Autodesk Fusion 360 part; units mm, degrees
(part 7 of 8)
equation "d1141 = ( ( ( keyRowOne ) + holderSpringY ) - holderSpringWidth / 2 ) + faceOriginV"
equation "d1142 = ( ( ( layoutGap + keycapSize / 2 + 2 * keyPitch ) - holderFrameX / 2 ) + ( holderFrameX / 2 - holderWidth / 2 + holderHookOverlap ) ) - ( ( layoutGap + keycapSize / 2 + 2 * keyPitch ) - holderFrameX / 2 )"
equation "d1143 = ( ( ( ( ( keyRowOne ) + holderSpringY ) - holderSpringWidth / 2 ) + faceOriginV ) + ( holderSpringWidth ) ) - ( ( ( ( keyRowOne ) + holderSpringY ) - holderSpringWidth / 2 ) + faceOriginV )"
equation "d1144 = -( holderHookThickness )"
equation "d1147 = ( layoutGap + keycapSize / 2 + 2 * keyPitch ) + holderWidth / 2 + holderFit"
equation "d1148 = ( ( ( keyRowOne ) + holderSpringY ) - holderSpringWidth / 2 - 0.6 mm ) + faceOriginV"
equation "d1149 = ( ( ( layoutGap + keycapSize / 2 + 2 * keyPitch ) + holderWidth / 2 + holderFit ) + ( holderFrameX / 2 - holderWidth / 2 - holderFit + 0.1 mm ) ) - ( ( layoutGap + keycapSize / 2 + 2 * keyPitch ) + holderWidth / 2 + holderFit )"
equation "d1150 = ( ( ( ( ( keyRowOne ) + holderSpringY ) - holderSpringWidth / 2 - 0.6 mm ) + faceOriginV ) + ( 0.6 mm ) ) - ( ( ( ( keyRowOne ) + holderSpringY ) - holderSpringWidth / 2 - 0.6 mm ) + faceOriginV )"
equation "d1151 = -( holderBottomDepth + holderHookThickness - shellWall - carrierClearance - carrierThickness - 1 mm + 0.2 mm )"
equation "d1153 = ( layoutGap + keycapSize / 2 + 2 * keyPitch ) + holderWidth / 2 + holderFit"
equation "d1154 = ( ( ( keyRowOne ) + holderSpringY ) + holderSpringWidth / 2 ) + faceOriginV"
equation "d1155 = ( ( ( layoutGap + keycapSize / 2 + 2 * keyPitch ) + holderWidth / 2 + holderFit ) + ( holderFrameX / 2 - holderWidth / 2 - holderFit + 0.1 mm ) ) - ( ( layoutGap + keycapSize / 2 + 2 * keyPitch ) + holderWidth / 2 + holderFit )"
equation "d1156 = ( ( ( ( ( keyRowOne ) + holderSpringY ) + holderSpringWidth / 2 ) + faceOriginV ) + ( 0.6 mm ) ) - ( ( ( ( keyRowOne ) + holderSpringY ) + holderSpringWidth / 2 ) + faceOriginV )"
equation "d1157 = -( holderBottomDepth + holderHookThickness - shellWall - carrierClearance - carrierThickness - 1 mm + 0.2 mm )"
equation "d1159 = ( layoutGap + keycapSize / 2 + 2 * keyPitch ) + holderWidth / 2 + holderFit"
equation "d1160 = ( ( ( keyRowOne ) + holderSpringY ) - holderSpringWidth / 2 ) + faceOriginV"
equation "d1161 = ( ( ( layoutGap + keycapSize / 2 + 2 * keyPitch ) + holderWidth / 2 + holderFit ) + ( holderFrameX / 2 - 0.8 mm - holderWidth / 2 - holderFit ) ) - ( ( layoutGap + keycapSize / 2 + 2 * keyPitch ) + holderWidth / 2 + holderFit )"
equation "d1162 = ( ( ( ( ( keyRowOne ) + holderSpringY ) - holderSpringWidth / 2 ) + faceOriginV ) + ( holderSpringWidth ) ) - ( ( ( ( keyRowOne ) + holderSpringY ) - holderSpringWidth / 2 ) + faceOriginV )"
equation "d1163 = -( holderHeight + holderHookThickness + 0.2 mm )"
equation "d1165 = ( layoutGap + keycapSize / 2 + 2 * keyPitch ) + holderWidth / 2 - holderHookOverlap"
equation "d1166 = ( ( ( keyRowOne ) + holderSpringY ) - holderSpringWidth / 2 ) + faceOriginV"
equation "d1167 = ( ( ( layoutGap + keycapSize / 2 + 2 * keyPitch ) + holderWidth / 2 - holderHookOverlap ) + ( holderFrameX / 2 - holderWidth / 2 + holderHookOverlap ) ) - ( ( layoutGap + keycapSize / 2 + 2 * keyPitch ) + holderWidth / 2 - holderHookOverlap )"
equation "d1168 = ( ( ( ( ( keyRowOne ) + holderSpringY ) - holderSpringWidth / 2 ) + faceOriginV ) + ( holderSpringWidth ) ) - ( ( ( ( keyRowOne ) + holderSpringY ) - holderSpringWidth / 2 ) + faceOriginV )"
equation "d1169 = -( holderHookThickness )"
equation "d1172 = ( layoutGap + keycapSize / 2 + 2 * keyPitch ) + ( -2.5 mm ) - 1.2 mm"
equation "d1173 = ( ( ( keyRowOne ) - 1.2 mm ) * cos(caseTilt) + ( holderBottomDepth + holderLidGap ) * sin(caseTilt) ) - 2.5 mm"
equation "d1174 = ( ( ( layoutGap + keycapSize / 2 + 2 * keyPitch ) + ( -2.5 mm ) - 1.2 mm ) + ( 2.4 mm ) ) - ( ( layoutGap + keycapSize / 2 + 2 * keyPitch ) + ( -2.5 mm ) - 1.2 mm )"
equation "d1175 = ( ( ( ( ( keyRowOne ) - 1.2 mm ) * cos(caseTilt) + ( holderBottomDepth + holderLidGap ) * sin(caseTilt) ) - 2.5 mm ) + ( 5 mm ) ) - ( ( ( ( keyRowOne ) - 1.2 mm ) * cos(caseTilt) + ( holderBottomDepth + holderLidGap ) * sin(caseTilt) ) - 2.5 mm )"
equation "d1176 = ( frontHeight + ( ( keyRowOne ) - 1.2 mm ) * sin(caseTilt) - ( holderBottomDepth + holderLidGap ) * cos(caseTilt) ) - bottomThickness - 2 mm"
equation "d1178 = ( layoutGap + keycapSize / 2 + 2 * keyPitch ) + ( -2.5 mm ) - 0.5 mm"
equation "d1179 = ( ( ( keyRowOne ) - 1.2 mm ) * cos(caseTilt) + ( holderBottomDepth + holderLidGap ) * sin(caseTilt) ) - 1.5 mm"
equation "d1180 = ( ( ( layoutGap + keycapSize / 2 + 2 * keyPitch ) + ( -2.5 mm ) - 0.5 mm ) + ( 1 mm ) ) - ( ( layoutGap + keycapSize / 2 + 2 * keyPitch ) + ( -2.5 mm ) - 0.5 mm )"
equation "d1181 = ( ( ( ( ( keyRowOne ) - 1.2 mm ) * cos(caseTilt) + ( holderBottomDepth + holderLidGap ) * sin(caseTilt) ) - 1.5 mm ) + ( 3 mm ) ) - ( ( ( ( keyRowOne ) - 1.2 mm ) * cos(caseTilt) + ( holderBottomDepth + holderLidGap ) * sin(caseTilt) ) - 1.5 mm )"
equation "d1182 = ( frontHeight + ( ( keyRowOne ) - 1.2 mm ) * sin(caseTilt) - ( holderBottomDepth + holderLidGap ) * cos(caseTilt) ) - bottomThickness + 0.5 mm"
equation "d1184 = ( ( layoutGap + keycapSize / 2 + 2 * keyPitch ) + ( -2.5 mm ) - 0.5 mm ) - 0.1 mm"
equation "d1185 = ( ( ( keyRowOne ) - 1.2 mm ) - 2 mm ) + faceOriginV"
equation "d1186 = ( ( ( ( layoutGap + keycapSize / 2 + 2 * keyPitch ) + ( -2.5 mm ) - 0.5 mm ) - 0.1 mm ) + ( 1.2 mm ) ) - ( ( ( layoutGap + keycapSize / 2 + 2 * keyPitch ) + ( -2.5 mm ) - 0.5 mm ) - 0.1 mm )"
equation "d1187 = ( ( ( ( ( keyRowOne ) - 1.2 mm ) - 2 mm ) + faceOriginV ) + ( 4 mm ) ) - ( ( ( ( keyRowOne ) - 1.2 mm ) - 2 mm ) + faceOriginV )"
equation "d1188 = rearHeight"
equation "d1190 = ( layoutGap + keycapSize / 2 + 2 * keyPitch ) + ( 2.5 mm ) - 1.2 mm"
equation "d1191 = ( ( ( keyRowOne ) - 1.2 mm ) * cos(caseTilt) + ( holderBottomDepth + holderLidGap ) * sin(caseTilt) ) - 2.5 mm"
equation "d1192 = ( ( ( layoutGap + keycapSize / 2 + 2 * keyPitch ) + ( 2.5 mm ) - 1.2 mm ) + ( 2.4 mm ) ) - ( ( layoutGap + keycapSize / 2 + 2 * keyPitch ) + ( 2.5 mm ) - 1.2 mm )"
equation "d1193 = ( ( ( ( ( keyRowOne ) - 1.2 mm ) * cos(caseTilt) + ( holderBottomDepth + holderLidGap ) * sin(caseTilt) ) - 2.5 mm ) + ( 5 mm ) ) - ( ( ( ( keyRowOne ) - 1.2 mm ) * cos(caseTilt) + ( holderBottomDepth + holderLidGap ) * sin(caseTilt) ) - 2.5 mm )"
equation "d1194 = ( frontHeight + ( ( keyRowOne ) - 1.2 mm ) * sin(caseTilt) - ( holderBottomDepth + holderLidGap ) * cos(caseTilt) ) - bottomThickness - 2 mm"
equation "d1196 = ( layoutGap + keycapSize / 2 + 2 * keyPitch ) + ( 2.5 mm ) - 0.5 mm"
equation "d1197 = ( ( ( keyRowOne ) - 1.2 mm ) * cos(caseTilt) + ( holderBottomDepth + holderLidGap ) * sin(caseTilt) ) - 1.5 mm"
equation "d1198 = ( ( ( layoutGap + keycapSize / 2 + 2 * keyPitch ) + ( 2.5 mm ) - 0.5 mm ) + ( 1 mm ) ) - ( ( layoutGap + keycapSize / 2 + 2 * keyPitch ) + ( 2.5 mm ) - 0.5 mm )"
equation "d1199 = ( ( ( ( ( keyRowOne ) - 1.2 mm ) * cos(caseTilt) + ( holderBottomDepth + holderLidGap ) * sin(caseTilt) ) - 1.5 mm ) + ( 3 mm ) ) - ( ( ( ( keyRowOne ) - 1.2 mm ) * cos(caseTilt) + ( holderBottomDepth + holderLidGap ) * sin(caseTilt) ) - 1.5 mm )"
equation "d1200 = ( frontHeight + ( ( keyRowOne ) - 1.2 mm ) * sin(caseTilt) - ( holderBottomDepth + holderLidGap ) * cos(caseTilt) ) - bottomThickness + 0.5 mm"
equation "d1202 = ( ( layoutGap + keycapSize / 2 + 2 * keyPitch ) + ( 2.5 mm ) - 0.5 mm ) - 0.1 mm"
equation "d1203 = ( ( ( keyRowOne ) - 1.2 mm ) - 2 mm ) + faceOriginV"
equation "d1204 = ( ( ( ( layoutGap + keycapSize / 2 + 2 * keyPitch ) + ( 2.5 mm ) - 0.5 mm ) - 0.1 mm ) + ( 1.2 mm ) ) - ( ( ( layoutGap + keycapSize / 2 + 2 * keyPitch ) + ( 2.5 mm ) - 0.5 mm ) - 0.1 mm )"
equation "d1205 = ( ( ( ( ( keyRowOne ) - 1.2 mm ) - 2 mm ) + faceOriginV ) + ( 4 mm ) ) - ( ( ( ( keyRowOne ) - 1.2 mm ) - 2 mm ) + faceOriginV )"
equation "d1206 = rearHeight"
equation "d1208 = ( layoutGap + keycapSize / 2 + 0 * keyPitch ) - holderFrameX / 2"
equation "d1209 = ( ( keyRowTwo ) - holderFrameY / 2 ) + faceOriginV"
equation "d1210 = ( ( ( layoutGap + keycapSize / 2 + 0 * keyPitch ) - holderFrameX / 2 ) + ( holderFrameX ) ) - ( ( layoutGap + keycapSize / 2 + 0 * keyPitch ) - holderFrameX / 2 )"
equation "d1211 = ( ( ( ( keyRowTwo ) - holderFrameY / 2 ) + faceOriginV ) + ( holderFrameY ) ) - ( ( ( keyRowTwo ) - holderFrameY / 2 ) + faceOriginV )"
equation "d1212 = -( holderBottomDepth + holderHookThickness - shellWall - carrierClearance - carrierThickness )"
equation "d1214 = ( layoutGap + keycapSize / 2 + 0 * keyPitch ) - holderSwitchVoid / 2"
equation "d1215 = ( ( keyRowTwo ) - holderSwitchVoid / 2 ) + faceOriginV"
equation "d1216 = ( ( ( layoutGap + keycapSize / 2 + 0 * keyPitch ) - holderSwitchVoid / 2 ) + ( holderSwitchVoid ) ) - ( ( layoutGap + keycapSize / 2 + 0 * keyPitch ) - holderSwitchVoid / 2 )"
equation "d1217 = ( ( ( ( keyRowTwo ) - holderSwitchVoid / 2 ) + faceOriginV ) + ( holderSwitchVoid ) ) - ( ( ( keyRowTwo ) - holderSwitchVoid / 2 ) + faceOriginV )"
equation "d1218 = -( holderTopDepth - shellWall - carrierClearance - carrierThickness )"
equation "d1220 = ( layoutGap + keycapSize / 2 + 0 * keyPitch ) - holderWidth / 2 - holderFit"
equation "d1221 = ( ( keyRowTwo ) - holderLength / 2 - holderFit ) + faceOriginV"
equation "d1222 = ( ( ( layoutGap + keycapSize / 2 + 0 * keyPitch ) - holderWidth / 2 - holderFit ) + ( holderWidth + 2 * holderFit ) ) - ( ( layoutGap + keycapSize / 2 + 0 * keyPitch ) - holderWidth / 2 - holderFit )"
equation "d1223 = ( ( ( ( keyRowTwo ) - holderLength / 2 - holderFit ) + faceOriginV ) + ( holderLength + 2 * holderFit ) ) - ( ( ( keyRowTwo ) - holderLength / 2 - holderFit ) + faceOriginV )"
equation "d1224 = -( holderHeight + holderHookThickness + 0.2 mm )"
equation "d1226 = ( layoutGap + keycapSize / 2 + 0 * keyPitch ) - holderFrameX / 2 - 0.1 mm"
equation "d1227 = ( ( ( keyRowTwo ) + holderSpringY ) - holderSpringWidth / 2 - 0.6 mm ) + faceOriginV"
equation "d1228 = ( ( ( layoutGap + keycapSize / 2 + 0 * keyPitch ) - holderFrameX / 2 - 0.1 mm ) + ( holderFrameX / 2 - holderWidth / 2 - holderFit + 0.1 mm ) ) - ( ( layoutGap + keycapSize / 2 + 0 * keyPitch ) - holderFrameX / 2 - 0.1 mm )"
equation "d1229 = ( ( ( ( ( keyRowTwo ) + holderSpringY ) - holderSpringWidth / 2 - 0.6 mm ) + faceOriginV ) + ( 0.6 mm ) ) - ( ( ( ( keyRowTwo ) + holderSpringY ) - holderSpringWidth / 2 - 0.6 mm ) + faceOriginV )"
equation "d1230 = -( holderBottomDepth + holderHookThickness - shellWall - carrierClearance - carrierThickness - 1 mm + 0.2 mm )"
equation "d1232 = ( layoutGap + keycapSize / 2 + 0 * keyPitch ) - holderFrameX / 2 - 0.1 mm"
equation "d1233 = ( ( ( keyRowTwo ) + holderSpringY ) + holderSpringWidth / 2 ) + faceOriginV"
equation "d1234 = ( ( ( layoutGap + keycapSize / 2 + 0 * keyPitch ) - holderFrameX / 2 - 0.1 mm ) + ( holderFrameX / 2 - holderWidth / 2 - holderFit + 0.1 mm ) ) - ( ( layoutGap + keycapSize / 2 + 0 * keyPitch ) - holderFrameX / 2 - 0.1 mm )"
equation "d1235 = ( ( ( ( ( keyRowTwo ) + holderSpringY ) + holderSpringWidth / 2 ) + faceOriginV ) + ( 0.6 mm ) ) - ( ( ( ( keyRowTwo ) + holderSpringY ) + holderSpringWidth / 2 ) + faceOriginV )"
equation "d1236 = -( holderBottomDepth + holderHookThickness - shellWall - carrierClearance - carrierThickness - 1 mm + 0.2 mm )"
equation "d1238 = ( layoutGap + keycapSize / 2 + 0 * keyPitch ) - holderFrameX / 2 + 0.8 mm"
equation "d1239 = ( ( ( keyRowTwo ) + holderSpringY ) - holderSpringWidth / 2 ) + faceOriginV"
equation "d1240 = ( ( ( layoutGap + keycapSize / 2 + 0 * keyPitch ) - holderFrameX / 2 + 0.8 mm ) + ( holderFrameX / 2 - 0.8 mm - holderWidth / 2 - holderFit ) ) - ( ( layoutGap + keycapSize / 2 + 0 * keyPitch ) - holderFrameX / 2 + 0.8 mm )"
equation "d1241 = ( ( ( ( ( keyRowTwo ) + holderSpringY ) - holderSpringWidth / 2 ) + faceOriginV ) + ( holderSpringWidth ) ) - ( ( ( ( keyRowTwo ) + holderSpringY ) - holderSpringWidth / 2 ) + faceOriginV )"
equation "d1242 = -( holderHeight + holderHookThickness + 0.2 mm )"
equation "d1244 = ( layoutGap + keycapSize / 2 + 0 * keyPitch ) - holderFrameX / 2"
equation "d1245 = ( ( ( keyRowTwo ) + holderSpringY ) - holderSpringWidth / 2 ) + faceOriginV"
equation "d1246 = ( ( ( layoutGap + keycapSize / 2 + 0 * keyPitch ) - holderFrameX / 2 ) + ( holderFrameX / 2 - holderWidth / 2 + holderHookOverlap ) ) - ( ( layoutGap + keycapSize / 2 + 0 * keyPitch ) - holderFrameX / 2 )"
equation "d1247 = ( ( ( ( ( keyRowTwo ) + holderSpringY ) - holderSpringWidth / 2 ) + faceOriginV ) + ( holderSpringWidth ) ) - ( ( ( ( keyRowTwo ) + holderSpringY ) - holderSpringWidth / 2 ) + faceOriginV )"
equation "d1248 = -( holderHookThickness )"
equation "d1251 = ( layoutGap + keycapSize / 2 + 0 * keyPitch ) + holderWidth / 2 + holderFit"
equation "d1252 = ( ( ( keyRowTwo ) + holderSpringY ) - holderSpringWidth / 2 - 0.6 mm ) + faceOriginV"
equation "d1253 = ( ( ( layoutGap + keycapSize / 2 + 0 * keyPitch ) + holderWidth / 2 + holderFit ) + ( holderFrameX / 2 - holderWidth / 2 - holderFit + 0.1 mm ) ) - ( ( layoutGap + keycapSize / 2 + 0 * keyPitch ) + holderWidth / 2 + holderFit )"
equation "d1254 = ( ( ( ( ( keyRowTwo ) + holderSpringY ) - holderSpringWidth / 2 - 0.6 mm ) + faceOriginV ) + ( 0.6 mm ) ) - ( ( ( ( keyRowTwo ) + holderSpringY ) - holderSpringWidth / 2 - 0.6 mm ) + faceOriginV )"
equation "d1255 = -( holderBottomDepth + holderHookThickness - shellWall - carrierClearance - carrierThickness - 1 mm + 0.2 mm )"
equation "d1257 = ( layoutGap + keycapSize / 2 + 0 * keyPitch ) + holderWidth / 2 + holderFit"
equation "d1258 = ( ( ( keyRowTwo ) + holderSpringY ) + holderSpringWidth / 2 ) + faceOriginV"
equation "d1259 = ( ( ( layoutGap + keycapSize / 2 + 0 * keyPitch ) + holderWidth / 2 + holderFit ) + ( holderFrameX / 2 - holderWidth / 2 - holderFit + 0.1 mm ) ) - ( ( layoutGap + keycapSize / 2 + 0 * keyPitch ) + holderWidth / 2 + holderFit )"
equation "d1260 = ( ( ( ( ( keyRowTwo ) + holderSpringY ) + holderSpringWidth / 2 ) + faceOriginV ) + ( 0.6 mm ) ) - ( ( ( ( keyRowTwo ) + holderSpringY ) + holderSpringWidth / 2 ) + faceOriginV )"
equation "d1261 = -( holderBottomDepth + holderHookThickness - shellWall - carrierClearance - carrierThickness - 1 mm + 0.2 mm )"
equation "d1263 = ( layoutGap + keycapSize / 2 + 0 * keyPitch ) + holderWidth / 2 + holderFit"
equation "d1264 = ( ( ( keyRowTwo ) + holderSpringY ) - holderSpringWidth / 2 ) + faceOriginV"
equation "d1265 = ( ( ( layoutGap + keycapSize / 2 + 0 * keyPitch ) + holderWidth / 2 + holderFit ) + ( holderFrameX / 2 - 0.8 mm - holderWidth / 2 - holderFit ) ) - ( ( layoutGap + keycapSize / 2 + 0 * keyPitch ) + holderWidth / 2 + holderFit )"
equation "d1266 = ( ( ( ( ( keyRowTwo ) + holderSpringY ) - holderSpringWidth / 2 ) + faceOriginV ) + ( holderSpringWidth ) ) - ( ( ( ( keyRowTwo ) + holderSpringY ) - holderSpringWidth / 2 ) + faceOriginV )"
equation "d1267 = -( holderHeight + holderHookThickness + 0.2 mm )"
equation "d1269 = ( layoutGap + keycapSize / 2 + 0 * keyPitch ) + holderWidth / 2 - holderHookOverlap"
equation "d1270 = ( ( ( keyRowTwo ) + holderSpringY ) - holderSpringWidth / 2 ) + faceOriginV"
equation "d1271 = ( ( ( layoutGap + keycapSize / 2 + 0 * keyPitch ) + holderWidth / 2 - holderHookOverlap ) + ( holderFrameX / 2 - holderWidth / 2 + holderHookOverlap ) ) - ( ( layoutGap + keycapSize / 2 + 0 * keyPitch ) + holderWidth / 2 - holderHookOverlap )"
equation "d1272 = ( ( ( ( ( keyRowTwo ) + holderSpringY ) - holderSpringWidth / 2 ) + faceOriginV ) + ( holderSpringWidth ) ) - ( ( ( ( keyRowTwo ) + holderSpringY ) - holderSpringWidth / 2 ) + faceOriginV )"
equation "d1273 = -( holderHookThickness )"
equation "d1276 = ( layoutGap + keycapSize / 2 + 0 * keyPitch ) + ( -2.5 mm ) - 1.2 mm"
equation "d1277 = ( ( ( keyRowTwo ) - 1.2 mm ) * cos(caseTilt) + ( holderBottomDepth + holderLidGap ) * sin(caseTilt) ) - 2.5 mm"
equation "d1278 = ( ( ( layoutGap + keycapSize / 2 + 0 * keyPitch ) + ( -2.5 mm ) - 1.2 mm ) + ( 2.4 mm ) ) - ( ( layoutGap + keycapSize / 2 + 0 * keyPitch ) + ( -2.5 mm ) - 1.2 mm )"
equation "d1279 = ( ( ( ( ( keyRowTwo ) - 1.2 mm ) * cos(caseTilt) + ( holderBottomDepth + holderLidGap ) * sin(caseTilt) ) - 2.5 mm ) + ( 5 mm ) ) - ( ( ( ( keyRowTwo ) - 1.2 mm ) * cos(caseTilt) + ( holderBottomDepth + holderLidGap ) * sin(caseTilt) ) - 2.5 mm )"
equation "d1280 = ( frontHeight + ( ( keyRowTwo ) - 1.2 mm ) * sin(caseTilt) - ( holderBottomDepth + holderLidGap ) * cos(caseTilt) ) - bottomThickness - 2 mm"
equation "d1282 = ( layoutGap + keycapSize / 2 + 0 * keyPitch ) + ( -2.5 mm ) - 0.5 mm"
equation "d1283 = ( ( ( keyRowTwo ) - 1.2 mm ) * cos(caseTilt) + ( holderBottomDepth + holderLidGap ) * sin(caseTilt) ) - 1.5 mm"
equation "d1284 = ( ( ( layoutGap + keycapSize / 2 + 0 * keyPitch ) + ( -2.5 mm ) - 0.5 mm ) + ( 1 mm ) ) - ( ( layoutGap + keycapSize / 2 + 0 * keyPitch ) + ( -2.5 mm ) - 0.5 mm )"
equation "d1285 = ( ( ( ( ( keyRowTwo ) - 1.2 mm ) * cos(caseTilt) + ( holderBottomDepth + holderLidGap ) * sin(caseTilt) ) - 1.5 mm ) + ( 3 mm ) ) - ( ( ( ( keyRowTwo ) - 1.2 mm ) * cos(caseTilt) + ( holderBottomDepth + holderLidGap ) * sin(caseTilt) ) - 1.5 mm )"
equation "d1286 = ( frontHeight + ( ( keyRowTwo ) - 1.2 mm ) * sin(caseTilt) - ( holderBottomDepth + holderLidGap ) * cos(caseTilt) ) - bottomThickness + 0.5 mm"
equation "d1288 = ( ( layoutGap + keycapSize / 2 + 0 * keyPitch ) + ( -2.5 mm ) - 0.5 mm ) - 0.1 mm"
equation "d1289 = ( ( ( keyRowTwo ) - 1.2 mm ) - 2 mm ) + faceOriginV"
equation "d1290 = ( ( ( ( layoutGap + keycapSize / 2 + 0 * keyPitch ) + ( -2.5 mm ) - 0.5 mm ) - 0.1 mm ) + ( 1.2 mm ) ) - ( ( ( layoutGap + keycapSize / 2 + 0 * keyPitch ) + ( -2.5 mm ) - 0.5 mm ) - 0.1 mm )"
equation "d1291 = ( ( ( ( ( keyRowTwo ) - 1.2 mm ) - 2 mm ) + faceOriginV ) + ( 4 mm ) ) - ( ( ( ( keyRowTwo ) - 1.2 mm ) - 2 mm ) + faceOriginV )"
equation "d1292 = rearHeight"
equation "d1294 = ( layoutGap + keycapSize / 2 + 0 * keyPitch ) + ( 2.5 mm ) - 1.2 mm"
equation "d1295 = ( ( ( keyRowTwo ) - 1.2 mm ) * cos(caseTilt) + ( holderBottomDepth + holderLidGap ) * sin(caseTilt) ) - 2.5 mm"
equation "d1296 = ( ( ( layoutGap + keycapSize / 2 + 0 * keyPitch ) + ( 2.5 mm ) - 1.2 mm ) + ( 2.4 mm ) ) - ( ( layoutGap + keycapSize / 2 + 0 * keyPitch ) + ( 2.5 mm ) - 1.2 mm )"
equation "d1297 = ( ( ( ( ( keyRowTwo ) - 1.2 mm ) * cos(caseTilt) + ( holderBottomDepth + holderLidGap ) * sin(caseTilt) ) - 2.5 mm ) + ( 5 mm ) ) - ( ( ( ( keyRowTwo ) - 1.2 mm ) * cos(caseTilt) + ( holderBottomDepth + holderLidGap ) * sin(caseTilt) ) - 2.5 mm )"
equation "d1298 = ( frontHeight + ( ( keyRowTwo ) - 1.2 mm ) * sin(caseTilt) - ( holderBottomDepth + holderLidGap ) * cos(caseTilt) ) - bottomThickness - 2 mm"
equation "d1300 = ( layoutGap + keycapSize / 2 + 0 * keyPitch ) + ( 2.5 mm ) - 0.5 mm"
equation "d1301 = ( ( ( keyRowTwo ) - 1.2 mm ) * cos(caseTilt) + ( holderBottomDepth + holderLidGap ) * sin(caseTilt) ) - 1.5 mm"
equation "d1302 = ( ( ( layoutGap + keycapSize / 2 + 0 * keyPitch ) + ( 2.5 mm ) - 0.5 mm ) + ( 1 mm ) ) - ( ( layoutGap + keycapSize / 2 + 0 * keyPitch ) + ( 2.5 mm ) - 0.5 mm )"
equation "d1303 = ( ( ( ( ( keyRowTwo ) - 1.2 mm ) * cos(caseTilt) + ( holderBottomDepth + holderLidGap ) * sin(caseTilt) ) - 1.5 mm ) + ( 3 mm ) ) - ( ( ( ( keyRowTwo ) - 1.2 mm ) * cos(caseTilt) + ( holderBottomDepth + holderLidGap ) * sin(caseTilt) ) - 1.5 mm )"
equation "d1304 = ( frontHeight + ( ( keyRowTwo ) - 1.2 mm ) * sin(caseTilt) - ( holderBottomDepth + holderLidGap ) * cos(caseTilt) ) - bottomThickness + 0.5 mm"
equation "d1306 = ( ( layoutGap + keycapSize / 2 + 0 * keyPitch ) + ( 2.5 mm ) - 0.5 mm ) - 0.1 mm"
equation "d1307 = ( ( ( keyRowTwo ) - 1.2 mm ) - 2 mm ) + faceOriginV"
equation "d1308 = ( ( ( ( layoutGap + keycapSize / 2 + 0 * keyPitch ) + ( 2.5 mm ) - 0.5 mm ) - 0.1 mm ) + ( 1.2 mm ) ) - ( ( ( layoutGap + keycapSize / 2 + 0 * keyPitch ) + ( 2.5 mm ) - 0.5 mm ) - 0.1 mm )"
equation "d1309 = ( ( ( ( ( keyRowTwo ) - 1.2 mm ) - 2 mm ) + faceOriginV ) + ( 4 mm ) ) - ( ( ( ( keyRowTwo ) - 1.2 mm ) - 2 mm ) + faceOriginV )"
equation "d1310 = rearHeight"
equation "d1312 = ( layoutGap + keycapSize / 2 + 1 * keyPitch ) - holderFrameX / 2"
equation "d1313 = ( ( keyRowTwo ) - holderFrameY / 2 ) + faceOriginV"
equation "d1314 = ( ( ( layoutGap + keycapSize / 2 + 1 * keyPitch ) - holderFrameX / 2 ) + ( holderFrameX ) ) - ( ( layoutGap + keycapSize / 2 + 1 * keyPitch ) - holderFrameX / 2 )"
equation "d1315 = ( ( ( ( keyRowTwo ) - holderFrameY / 2 ) + faceOriginV ) + ( holderFrameY ) ) - ( ( ( keyRowTwo ) - holderFrameY / 2 ) + faceOriginV )"
equation "d1316 = -( holderBottomDepth + holderHookThickness - shellWall - carrierClearance - carrierThickness )"
equation "d1318 = ( layoutGap + keycapSize / 2 + 1 * keyPitch ) - holderSwitchVoid / 2"
equation "d1319 = ( ( keyRowTwo ) - holderSwitchVoid / 2 ) + faceOriginV"
equation "d1320 = ( ( ( layoutGap + keycapSize / 2 + 1 * keyPitch ) - holderSwitchVoid / 2 ) + ( holderSwitchVoid ) ) - ( ( layoutGap + keycapSize / 2 + 1 * keyPitch ) - holderSwitchVoid / 2 )"
equation "d1321 = ( ( ( ( keyRowTwo ) - holderSwitchVoid / 2 ) + faceOriginV ) + ( holderSwitchVoid ) ) - ( ( ( keyRowTwo ) - holderSwitchVoid / 2 ) + faceOriginV )"
equation "d1322 = -( holderTopDepth - shellWall - carrierClearance - carrierThickness )"
equation "d1324 = ( layoutGap + keycapSize / 2 + 1 * keyPitch ) - holderWidth / 2 - holderFit"
equation "d1325 = ( ( keyRowTwo ) - holderLength / 2 - holderFit ) + faceOriginV"
equation "d1326 = ( ( ( layoutGap + keycapSize / 2 + 1 * keyPitch ) - holderWidth / 2 - holderFit ) + ( holderWidth + 2 * holderFit ) ) - ( ( layoutGap + keycapSize / 2 + 1 * keyPitch ) - holderWidth / 2 - holderFit )"
equation "d1327 = ( ( ( ( keyRowTwo ) - holderLength / 2 - holderFit ) + faceOriginV ) + ( holderLength + 2 * holderFit ) ) - ( ( ( keyRowTwo ) - holderLength / 2 - holderFit ) + faceOriginV )"
equation "d1328 = -( holderHeight + holderHookThickness + 0.2 mm )"
equation "d1330 = ( layoutGap + keycapSize / 2 + 1 * keyPitch ) - holderFrameX / 2 - 0.1 mm"
equation "d1331 = ( ( ( keyRowTwo ) + holderSpringY ) - holderSpringWidth / 2 - 0.6 mm ) + faceOriginV"
equation "d1332 = ( ( ( layoutGap + keycapSize / 2 + 1 * keyPitch ) - holderFrameX / 2 - 0.1 mm ) + ( holderFrameX / 2 - holderWidth / 2 - holderFit + 0.1 mm ) ) - ( ( layoutGap + keycapSize / 2 + 1 * keyPitch ) - holderFrameX / 2 - 0.1 mm )"
equation "d1333 = ( ( ( ( ( keyRowTwo ) + holderSpringY ) - holderSpringWidth / 2 - 0.6 mm ) + faceOriginV ) + ( 0.6 mm ) ) - ( ( ( ( keyRowTwo ) + holderSpringY ) - holderSpringWidth / 2 - 0.6 mm ) + faceOriginV )"
equation "d1334 = -( holderBottomDepth + holderHookThickness - shellWall - carrierClearance - carrierThickness - 1 mm + 0.2 mm )"
equation "d1336 = ( layoutGap + keycapSize / 2 + 1 * keyPitch ) - holderFrameX / 2 - 0.1 mm"
equation "d1337 = ( ( ( keyRowTwo ) + holderSpringY ) + holderSpringWidth / 2 ) + faceOriginV"
equation "d1338 = ( ( ( layoutGap + keycapSize / 2 + 1 * keyPitch ) - holderFrameX / 2 - 0.1 mm ) + ( holderFrameX / 2 - holderWidth / 2 - holderFit + 0.1 mm ) ) - ( ( layoutGap + keycapSize / 2 + 1 * keyPitch ) - holderFrameX / 2 - 0.1 mm )"
equation "d1339 = ( ( ( ( ( keyRowTwo ) + holderSpringY ) + holderSpringWidth / 2 ) + faceOriginV ) + ( 0.6 mm ) ) - ( ( ( ( keyRowTwo ) + holderSpringY ) + holderSpringWidth / 2 ) + faceOriginV )"
equation "d1340 = -( holderBottomDepth + holderHookThickness - shellWall - carrierClearance - carrierThickness - 1 mm + 0.2 mm )"
equation "d1342 = ( layoutGap + keycapSize / 2 + 1 * keyPitch ) - holderFrameX / 2 + 0.8 mm"
equation "d1343 = ( ( ( keyRowTwo ) + holderSpringY ) - holderSpringWidth / 2 ) + faceOriginV"
equation "d1344 = ( ( ( layoutGap + keycapSize / 2 + 1 * keyPitch ) - holderFrameX / 2 + 0.8 mm ) + ( holderFrameX / 2 - 0.8 mm - holderWidth / 2 - holderFit ) ) - ( ( layoutGap + keycapSize / 2 + 1 * keyPitch ) - holderFrameX / 2 + 0.8 mm )"
equation "d1345 = ( ( ( ( ( keyRowTwo ) + holderSpringY ) - holderSpringWidth / 2 ) + faceOriginV ) + ( holderSpringWidth ) ) - ( ( ( ( keyRowTwo ) + holderSpringY ) - holderSpringWidth / 2 ) + faceOriginV )"
equation "d1346 = -( holderHeight + holderHookThickness + 0.2 mm )"
equation "d1348 = ( layoutGap + keycapSize / 2 + 1 * keyPitch ) - holderFrameX / 2"
equation "d1349 = ( ( ( keyRowTwo ) + holderSpringY ) - holderSpringWidth / 2 ) + faceOriginV"
equation "d1350 = ( ( ( layoutGap + keycapSize / 2 + 1 * keyPitch ) - holderFrameX / 2 ) + ( holderFrameX / 2 - holderWidth / 2 + holderHookOverlap ) ) - ( ( layoutGap + keycapSize / 2 + 1 * keyPitch ) - holderFrameX / 2 )"
equation "d1351 = ( ( ( ( ( keyRowTwo ) + holderSpringY ) - holderSpringWidth / 2 ) + faceOriginV ) + ( holderSpringWidth ) ) - ( ( ( ( keyRowTwo ) + holderSpringY ) - holderSpringWidth / 2 ) + faceOriginV )"
equation "d1352 = -( holderHookThickness )"
equation "d1355 = ( layoutGap + keycapSize / 2 + 1 * keyPitch ) + holderWidth / 2 + holderFit"
equation "d1356 = ( ( ( keyRowTwo ) + holderSpringY ) - holderSpringWidth / 2 - 0.6 mm ) + faceOriginV"
equation "d1357 = ( ( ( layoutGap + keycapSize / 2 + 1 * keyPitch ) + holderWidth / 2 + holderFit ) + ( holderFrameX / 2 - holderWidth / 2 - holderFit + 0.1 mm ) ) - ( ( layoutGap + keycapSize / 2 + 1 * keyPitch ) + holderWidth / 2 + holderFit )"
equation "d1358 = ( ( ( ( ( keyRowTwo ) + holderSpringY ) - holderSpringWidth / 2 - 0.6 mm ) + faceOriginV ) + ( 0.6 mm ) ) - ( ( ( ( keyRowTwo ) + holderSpringY ) - holderSpringWidth / 2 - 0.6 mm ) + faceOriginV )"
equation "d1359 = -( holderBottomDepth + holderHookThickness - shellWall - carrierClearance - carrierThickness - 1 mm + 0.2 mm )"
equation "d1361 = ( layoutGap + keycapSize / 2 + 1 * keyPitch ) + holderWidth / 2 + holderFit"
equation "d1362 = ( ( ( keyRowTwo ) + holderSpringY ) + holderSpringWidth / 2 ) + faceOriginV"
equation "d1363 = ( ( ( layoutGap + keycapSize / 2 + 1 * keyPitch ) + holderWidth / 2 + holderFit ) + ( holderFrameX / 2 - holderWidth / 2 - holderFit + 0.1 mm ) ) - ( ( layoutGap + keycapSize / 2 + 1 * keyPitch ) + holderWidth / 2 + holderFit )"
equation "d1364 = ( ( ( ( ( keyRowTwo ) + holderSpringY ) + holderSpringWidth / 2 ) + faceOriginV ) + ( 0.6 mm ) ) - ( ( ( ( keyRowTwo ) + holderSpringY ) + holderSpringWidth / 2 ) + faceOriginV )"
equation "d1365 = -( holderBottomDepth + holderHookThickness - shellWall - carrierClearance - carrierThickness - 1 mm + 0.2 mm )"
equation "d1367 = ( layoutGap + keycapSize / 2 + 1 * keyPitch ) + holderWidth / 2 + holderFit"
equation "d1368 = ( ( ( keyRowTwo ) + holderSpringY ) - holderSpringWidth / 2 ) + faceOriginV"
equation "d1369 = ( ( ( layoutGap + keycapSize / 2 + 1 * keyPitch ) + holderWidth / 2 + holderFit ) + ( holderFrameX / 2 - 0.8 mm - holderWidth / 2 - holderFit ) ) - ( ( layoutGap + keycapSize / 2 + 1 * keyPitch ) + holderWidth / 2 + holderFit )"
equation "d1370 = ( ( ( ( ( keyRowTwo ) + holderSpringY ) - holderSpringWidth / 2 ) + faceOriginV ) + ( holderSpringWidth ) ) - ( ( ( ( keyRowTwo ) + holderSpringY ) - holderSpringWidth / 2 ) + faceOriginV )"
equation "d1371 = -( holderHeight + holderHookThickness + 0.2 mm )"
equation "d1373 = ( layoutGap + keycapSize / 2 + 1 * keyPitch ) + holderWidth / 2 - holderHookOverlap"
equation "d1374 = ( ( ( keyRowTwo ) + holderSpringY ) - holderSpringWidth / 2 ) + faceOriginV"
equation "d1375 = ( ( ( layoutGap + keycapSize / 2 + 1 * keyPitch ) + holderWidth / 2 - holderHookOverlap ) + ( holderFrameX / 2 - holderWidth / 2 + holderHookOverlap ) ) - ( ( layoutGap + keycapSize / 2 + 1 * keyPitch ) + holderWidth / 2 - holderHookOverlap )"
equation "d1376 = ( ( ( ( ( keyRowTwo ) + holderSpringY ) - holderSpringWidth / 2 ) + faceOriginV ) + ( holderSpringWidth ) ) - ( ( ( ( keyRowTwo ) + holderSpringY ) - holderSpringWidth / 2 ) + faceOriginV )"
equation "d1377 = -( holderHookThickness )"
equation "d1380 = ( layoutGap + keycapSize / 2 + 1 * keyPitch ) + ( -2.5 mm ) - 1.2 mm"
equation "d1381 = ( ( ( keyRowTwo ) - 1.2 mm ) * cos(caseTilt) + ( holderBottomDepth + holderLidGap ) * sin(caseTilt) ) - 2.5 mm"
equation "d1382 = ( ( ( layoutGap + keycapSize / 2 + 1 * keyPitch ) + ( -2.5 mm ) - 1.2 mm ) + ( 2.4 mm ) ) - ( ( layoutGap + keycapSize / 2 + 1 * keyPitch ) + ( -2.5 mm ) - 1.2 mm )"
equation "d1383 = ( ( ( ( ( keyRowTwo ) - 1.2 mm ) * cos(caseTilt) + ( holderBottomDepth + holderLidGap ) * sin(caseTilt) ) - 2.5 mm ) + ( 5 mm ) ) - ( ( ( ( keyRowTwo ) - 1.2 mm ) * cos(caseTilt) + ( holderBottomDepth + holderLidGap ) * sin(caseTilt) ) - 2.5 mm )"
equation "d1384 = ( frontHeight + ( ( keyRowTwo ) - 1.2 mm ) * sin(caseTilt) - ( holderBottomDepth + holderLidGap ) * cos(caseTilt) ) - bottomThickness - 2 mm"
equation "d1386 = ( layoutGap + keycapSize / 2 + 1 * keyPitch ) + ( -2.5 mm ) - 0.5 mm"
equation "d1387 = ( ( ( keyRowTwo ) - 1.2 mm ) * cos(caseTilt) + ( holderBottomDepth + holderLidGap ) * sin(caseTilt) ) - 1.5 mm"
equation "d1388 = ( ( ( layoutGap + keycapSize / 2 + 1 * keyPitch ) + ( -2.5 mm ) - 0.5 mm ) + ( 1 mm ) ) - ( ( layoutGap + keycapSize / 2 + 1 * keyPitch ) + ( -2.5 mm ) - 0.5 mm )"
equation "d1389 = ( ( ( ( ( keyRowTwo ) - 1.2 mm ) * cos(caseTilt) + ( holderBottomDepth + holderLidGap ) * sin(caseTilt) ) - 1.5 mm ) + ( 3 mm ) ) - ( ( ( ( keyRowTwo ) - 1.2 mm ) * cos(caseTilt) + ( holderBottomDepth + holderLidGap ) * sin(caseTilt) ) - 1.5 mm )"
equation "d1390 = ( frontHeight + ( ( keyRowTwo ) - 1.2 mm ) * sin(caseTilt) - ( holderBottomDepth + holderLidGap ) * cos(caseTilt) ) - bottomThickness + 0.5 mm"
equation "d1392 = ( ( layoutGap + keycapSize / 2 + 1 * keyPitch ) + ( -2.5 mm ) - 0.5 mm ) - 0.1 mm"
equation "d1393 = ( ( ( keyRowTwo ) - 1.2 mm ) - 2 mm ) + faceOriginV"
equation "d1394 = ( ( ( ( layoutGap + keycapSize / 2 + 1 * keyPitch ) + ( -2.5 mm ) - 0.5 mm ) - 0.1 mm ) + ( 1.2 mm ) ) - ( ( ( layoutGap + keycapSize / 2 + 1 * keyPitch ) + ( -2.5 mm ) - 0.5 mm ) - 0.1 mm )"
equation "d1395 = ( ( ( ( ( keyRowTwo ) - 1.2 mm ) - 2 mm ) + faceOriginV ) + ( 4 mm ) ) - ( ( ( ( keyRowTwo ) - 1.2 mm ) - 2 mm ) + faceOriginV )"
equation "d1396 = rearHeight"
equation "d1398 = ( layoutGap + keycapSize / 2 + 1 * keyPitch ) + ( 2.5 mm ) - 1.2 mm"
equation "d1399 = ( ( ( keyRowTwo ) - 1.2 mm ) * cos(caseTilt) + ( holderBottomDepth + holderLidGap ) * sin(caseTilt) ) - 2.5 mm"
equation "d1400 = ( ( ( layoutGap + keycapSize / 2 + 1 * keyPitch ) + ( 2.5 mm ) - 1.2 mm ) + ( 2.4 mm ) ) - ( ( layoutGap + keycapSize / 2 + 1 * keyPitch ) + ( 2.5 mm ) - 1.2 mm )"
equation "d1401 = ( ( ( ( ( keyRowTwo ) - 1.2 mm ) * cos(caseTilt) + ( holderBottomDepth + holderLidGap ) * sin(caseTilt) ) - 2.5 mm ) + ( 5 mm ) ) - ( ( ( ( keyRowTwo ) - 1.2 mm ) * cos(caseTilt) + ( holderBottomDepth + holderLidGap ) * sin(caseTilt) ) - 2.5 mm )"
equation "d1402 = ( frontHeight + ( ( keyRowTwo ) - 1.2 mm ) * sin(caseTilt) - ( holderBottomDepth + holderLidGap ) * cos(caseTilt) ) - bottomThickness - 2 mm"
equation "d1404 = ( layoutGap + keycapSize / 2 + 1 * keyPitch ) + ( 2.5 mm ) - 0.5 mm"
equation "d1405 = ( ( ( keyRowTwo ) - 1.2 mm ) * cos(caseTilt) + ( holderBottomDepth + holderLidGap ) * sin(caseTilt) ) - 1.5 mm"
equation "d1406 = ( ( ( layoutGap + keycapSize / 2 + 1 * keyPitch ) + ( 2.5 mm ) - 0.5 mm ) + ( 1 mm ) ) - ( ( layoutGap + keycapSize / 2 + 1 * keyPitch ) + ( 2.5 mm ) - 0.5 mm )"
equation "d1407 = ( ( ( ( ( keyRowTwo ) - 1.2 mm ) * cos(caseTilt) + ( holderBottomDepth + holderLidGap ) * sin(caseTilt) ) - 1.5 mm ) + ( 3 mm ) ) - ( ( ( ( keyRowTwo ) - 1.2 mm ) * cos(caseTilt) + ( holderBottomDepth + holderLidGap ) * sin(caseTilt) ) - 1.5 mm )"
equation "d1408 = ( frontHeight + ( ( keyRowTwo ) - 1.2 mm ) * sin(caseTilt) - ( holderBottomDepth + holderLidGap ) * cos(caseTilt) ) - bottomThickness + 0.5 mm"
equation "d1410 = ( ( layoutGap + keycapSize / 2 + 1 * keyPitch ) + ( 2.5 mm ) - 0.5 mm ) - 0.1 mm"
equation "d1411 = ( ( ( keyRowTwo ) - 1.2 mm ) - 2 mm ) + faceOriginV"
equation "d1412 = ( ( ( ( layoutGap + keycapSize / 2 + 1 * keyPitch ) + ( 2.5 mm ) - 0.5 mm ) - 0.1 mm ) + ( 1.2 mm ) ) - ( ( ( layoutGap + keycapSize / 2 + 1 * keyPitch ) + ( 2.5 mm ) - 0.5 mm ) - 0.1 mm )"
equation "d1413 = ( ( ( ( ( keyRowTwo ) - 1.2 mm ) - 2 mm ) + faceOriginV ) + ( 4 mm ) ) - ( ( ( ( keyRowTwo ) - 1.2 mm ) - 2 mm ) + faceOriginV )"
equation "d1414 = rearHeight"
equation "d1416 = ( layoutGap + keycapSize / 2 + 2 * keyPitch ) - holderFrameX / 2"
equation "d1417 = ( ( keyRowTwo ) - holderFrameY / 2 ) + faceOriginV"
equation "d1418 = ( ( ( layoutGap + keycapSize / 2 + 2 * keyPitch ) - holderFrameX / 2 ) + ( holderFrameX ) ) - ( ( layoutGap + keycapSize / 2 + 2 * keyPitch ) - holderFrameX / 2 )"
equation "d1419 = ( ( ( ( keyRowTwo ) - holderFrameY / 2 ) + faceOriginV ) + ( holderFrameY ) ) - ( ( ( keyRowTwo ) - holderFrameY / 2 ) + faceOriginV )"
equation "d1420 = -( holderBottomDepth + holderHookThickness - shellWall - carrierClearance - carrierThickness )"
equation "d1422 = ( layoutGap + keycapSize / 2 + 2 * keyPitch ) - holderSwitchVoid / 2"
equation "d1423 = ( ( keyRowTwo ) - holderSwitchVoid / 2 ) + faceOriginV"
equation "d1424 = ( ( ( layoutGap + keycapSize / 2 + 2 * keyPitch ) - holderSwitchVoid / 2 ) + ( holderSwitchVoid ) ) - ( ( layoutGap + keycapSize / 2 + 2 * keyPitch ) - holderSwitchVoid / 2 )"
equation "d1425 = ( ( ( ( keyRowTwo ) - holderSwitchVoid / 2 ) + faceOriginV ) + ( holderSwitchVoid ) ) - ( ( ( keyRowTwo ) - holderSwitchVoid / 2 ) + faceOriginV )"
equation "d1426 = -( holderTopDepth - shellWall - carrierClearance - carrierThickness )"
equation "d1428 = ( layoutGap + keycapSize / 2 + 2 * keyPitch ) - holderWidth / 2 - holderFit"
equation "d1429 = ( ( keyRowTwo ) - holderLength / 2 - holderFit ) + faceOriginV"
equation "d1430 = ( ( ( layoutGap + keycapSize / 2 + 2 * keyPitch ) - holderWidth / 2 - holderFit ) + ( holderWidth + 2 * holderFit ) ) - ( ( layoutGap + keycapSize / 2 + 2 * keyPitch ) - holderWidth / 2 - holderFit )"
equation "d1431 = ( ( ( ( keyRowTwo ) - holderLength / 2 - holderFit ) + faceOriginV ) + ( holderLength + 2 * holderFit ) ) - ( ( ( keyRowTwo ) - holderLength / 2 - holderFit ) + faceOriginV )"
equation "d1432 = -( holderHeight + holderHookThickness + 0.2 mm )"
equation "d1434 = ( layoutGap + keycapSize / 2 + 2 * keyPitch ) - holderFrameX / 2 - 0.1 mm"
equation "d1435 = ( ( ( keyRowTwo ) + holderSpringY ) - holderSpringWidth / 2 - 0.6 mm ) + faceOriginV"
equation "d1436 = ( ( ( layoutGap + keycapSize / 2 + 2 * keyPitch ) - holderFrameX / 2 - 0.1 mm ) + ( holderFrameX / 2 - holderWidth / 2 - holderFit + 0.1 mm ) ) - ( ( layoutGap + keycapSize / 2 + 2 * keyPitch ) - holderFrameX / 2 - 0.1 mm )"
equation "d1437 = ( ( ( ( ( keyRowTwo ) + holderSpringY ) - holderSpringWidth / 2 - 0.6 mm ) + faceOriginV ) + ( 0.6 mm ) ) - ( ( ( ( keyRowTwo ) + holderSpringY ) - holderSpringWidth / 2 - 0.6 mm ) + faceOriginV )"
equation "d1438 = -( holderBottomDepth + holderHookThickness - shellWall - carrierClearance - carrierThickness - 1 mm + 0.2 mm )"
equation "d1440 = ( layoutGap + keycapSize / 2 + 2 * keyPitch ) - holderFrameX / 2 - 0.1 mm"
equation "d1441 = ( ( ( keyRowTwo ) + holderSpringY ) + holderSpringWidth / 2 ) + faceOriginV"
equation "d1442 = ( ( ( layoutGap + keycapSize / 2 + 2 * keyPitch ) - holderFrameX / 2 - 0.1 mm ) + ( holderFrameX / 2 - holderWidth / 2 - holderFit + 0.1 mm ) ) - ( ( layoutGap + keycapSize / 2 + 2 * keyPitch ) - holderFrameX / 2 - 0.1 mm )"
equation "d1443 = ( ( ( ( ( keyRowTwo ) + holderSpringY ) + holderSpringWidth / 2 ) + faceOriginV ) + ( 0.6 mm ) ) - ( ( ( ( keyRowTwo ) + holderSpringY ) + holderSpringWidth / 2 ) + faceOriginV )"
equation "d1444 = -( holderBottomDepth + holderHookThickness - shellWall - carrierClearance - carrierThickness - 1 mm + 0.2 mm )"
equation "d1446 = ( layoutGap + keycapSize / 2 + 2 * keyPitch ) - holderFrameX / 2 + 0.8 mm"
equation "d1447 = ( ( ( keyRowTwo ) + holderSpringY ) - holderSpringWidth / 2 ) + faceOriginV"
equation "d1448 = ( ( ( layoutGap + keycapSize / 2 + 2 * keyPitch ) - holderFrameX / 2 + 0.8 mm ) + ( holderFrameX / 2 - 0.8 mm - holderWidth / 2 - holderFit ) ) - ( ( layoutGap + keycapSize / 2 + 2 * keyPitch ) - holderFrameX / 2 + 0.8 mm )"
equation "d1449 = ( ( ( ( ( keyRowTwo ) + holderSpringY ) - holderSpringWidth / 2 ) + faceOriginV ) + ( holderSpringWidth ) ) - ( ( ( ( keyRowTwo ) + holderSpringY ) - holderSpringWidth / 2 ) + faceOriginV )"
equation "d1450 = -( holderHeight + holderHookThickness + 0.2 mm )"
equation "d1452 = ( layoutGap + keycapSize / 2 + 2 * keyPitch ) - holderFrameX / 2"
equation "d1453 = ( ( ( keyRowTwo ) + holderSpringY ) - holderSpringWidth / 2 ) + faceOriginV"
equation "d1454 = ( ( ( layoutGap + keycapSize / 2 + 2 * keyPitch ) - holderFrameX / 2 ) + ( holderFrameX / 2 - holderWidth / 2 + holderHookOverlap ) ) - ( ( layoutGap + keycapSize / 2 + 2 * keyPitch ) - holderFrameX / 2 )"
equation "d1455 = ( ( ( ( ( keyRowTwo ) + holderSpringY ) - holderSpringWidth / 2 ) + faceOriginV ) + ( holderSpringWidth ) ) - ( ( ( ( keyRowTwo ) + holderSpringY ) - holderSpringWidth / 2 ) + faceOriginV )"
equation "d1456 = -( holderHookThickness )"
equation "d1459 = ( layoutGap + keycapSize / 2 + 2 * keyPitch ) + holderWidth / 2 + holderFit"
equation "d1460 = ( ( ( keyRowTwo ) + holderSpringY ) - holderSpringWidth / 2 - 0.6 mm ) + faceOriginV"
equation "d1461 = ( ( ( layoutGap + keycapSize / 2 + 2 * keyPitch ) + holderWidth / 2 + holderFit ) + ( holderFrameX / 2 - holderWidth / 2 - holderFit + 0.1 mm ) ) - ( ( layoutGap + keycapSize / 2 + 2 * keyPitch ) + holderWidth / 2 + holderFit )"
equation "d1462 = ( ( ( ( ( keyRowTwo ) + holderSpringY ) - holderSpringWidth / 2 - 0.6 mm ) + faceOriginV ) + ( 0.6 mm ) ) - ( ( ( ( keyRowTwo ) + holderSpringY ) - holderSpringWidth / 2 - 0.6 mm ) + faceOriginV )"
equation "d1463 = -( holderBottomDepth + holderHookThickness - shellWall - carrierClearance - carrierThickness - 1 mm + 0.2 mm )"
equation "d1465 = ( layoutGap + keycapSize / 2 + 2 * keyPitch ) + holderWidth / 2 + holderFit"
equation "d1466 = ( ( ( keyRowTwo ) + holderSpringY ) + holderSpringWidth / 2 ) + faceOriginV"
equation "d1467 = ( ( ( layoutGap + keycapSize / 2 + 2 * keyPitch ) + holderWidth / 2 + holderFit ) + ( holderFrameX / 2 - holderWidth / 2 - holderFit + 0.1 mm ) ) - ( ( layoutGap + keycapSize / 2 + 2 * keyPitch ) + holderWidth / 2 + holderFit )"
equation "d1468 = ( ( ( ( ( keyRowTwo ) + holderSpringY ) + holderSpringWidth / 2 ) + faceOriginV ) + ( 0.6 mm ) ) - ( ( ( ( keyRowTwo ) + holderSpringY ) + holderSpringWidth / 2 ) + faceOriginV )"
equation "d1469 = -( holderBottomDepth + holderHookThickness - shellWall - carrierClearance - carrierThickness - 1 mm + 0.2 mm )"
equation "d1471 = ( layoutGap + keycapSize / 2 + 2 * keyPitch ) + holderWidth / 2 + holderFit"
equation "d1472 = ( ( ( keyRowTwo ) + holderSpringY ) - holderSpringWidth / 2 ) + faceOriginV"
equation "d1473 = ( ( ( layoutGap + keycapSize / 2 + 2 * keyPitch ) + holderWidth / 2 + holderFit ) + ( holderFrameX / 2 - 0.8 mm - holderWidth / 2 - holderFit ) ) - ( ( layoutGap + keycapSize / 2 + 2 * keyPitch ) + holderWidth / 2 + holderFit )"
equation "d1474 = ( ( ( ( ( keyRowTwo ) + holderSpringY ) - holderSpringWidth / 2 ) + faceOriginV ) + ( holderSpringWidth ) ) - ( ( ( ( keyRowTwo ) + holderSpringY ) - holderSpringWidth / 2 ) + faceOriginV )"
equation "d1475 = -( holderHeight + holderHookThickness + 0.2 mm )"
equation "d1477 = ( layoutGap + keycapSize / 2 + 2 * keyPitch ) + holderWidth / 2 - holderHookOverlap"
equation "d1478 = ( ( ( keyRowTwo ) + holderSpringY ) - holderSpringWidth / 2 ) + faceOriginV"
equation "d1479 = ( ( ( layoutGap + keycapSize / 2 + 2 * keyPitch ) + holderWidth / 2 - holderHookOverlap ) + ( holderFrameX / 2 - holderWidth / 2 + holderHookOverlap ) ) - ( ( layoutGap + keycapSize / 2 + 2 * keyPitch ) + holderWidth / 2 - holderHookOverlap )"
equation "d1480 = ( ( ( ( ( keyRowTwo ) + holderSpringY ) - holderSpringWidth / 2 ) + faceOriginV ) + ( holderSpringWidth ) ) - ( ( ( ( keyRowTwo ) + holderSpringY ) - holderSpringWidth / 2 ) + faceOriginV )"
equation "d1481 = -( holderHookThickness )"
equation "d1484 = ( layoutGap + keycapSize / 2 + 2 * keyPitch ) + ( -2.5 mm ) - 1.2 mm"
equation "d1485 = ( ( ( keyRowTwo ) - 1.2 mm ) * cos(caseTilt) + ( holderBottomDepth + holderLidGap ) * sin(caseTilt) ) - 2.5 mm"
equation "d1486 = ( ( ( layoutGap + keycapSize / 2 + 2 * keyPitch ) + ( -2.5 mm ) - 1.2 mm ) + ( 2.4 mm ) ) - ( ( layoutGap + keycapSize / 2 + 2 * keyPitch ) + ( -2.5 mm ) - 1.2 mm )"
equation "d1487 = ( ( ( ( ( keyRowTwo ) - 1.2 mm ) * cos(caseTilt) + ( holderBottomDepth + holderLidGap ) * sin(caseTilt) ) - 2.5 mm ) + ( 5 mm ) ) - ( ( ( ( keyRowTwo ) - 1.2 mm ) * cos(caseTilt) + ( holderBottomDepth + holderLidGap ) * sin(caseTilt) ) - 2.5 mm )"
equation "d1488 = ( frontHeight + ( ( keyRowTwo ) - 1.2 mm ) * sin(caseTilt) - ( holderBottomDepth + holderLidGap ) * cos(caseTilt) ) - bottomThickness - 2 mm"
equation "d1490 = ( layoutGap + keycapSize / 2 + 2 * keyPitch ) + ( -2.5 mm ) - 0.5 mm"
equation "d1491 = ( ( ( keyRowTwo ) - 1.2 mm ) * cos(caseTilt) + ( holderBottomDepth + holderLidGap ) * sin(caseTilt) ) - 1.5 mm"
equation "d1492 = ( ( ( layoutGap + keycapSize / 2 + 2 * keyPitch ) + ( -2.5 mm ) - 0.5 mm ) + ( 1 mm ) ) - ( ( layoutGap + keycapSize / 2 + 2 * keyPitch ) + ( -2.5 mm ) - 0.5 mm )"
equation "d1493 = ( ( ( ( ( keyRowTwo ) - 1.2 mm ) * cos(caseTilt) + ( holderBottomDepth + holderLidGap ) * sin(caseTilt) ) - 1.5 mm ) + ( 3 mm ) ) - ( ( ( ( keyRowTwo ) - 1.2 mm ) * cos(caseTilt) + ( holderBottomDepth + holderLidGap ) * sin(caseTilt) ) - 1.5 mm )"
equation "d1494 = ( frontHeight + ( ( keyRowTwo ) - 1.2 mm ) * sin(caseTilt) - ( holderBottomDepth + holderLidGap ) * cos(caseTilt) ) - bottomThickness + 0.5 mm"
equation "d1496 = ( ( layoutGap + keycapSize / 2 + 2 * keyPitch ) + ( -2.5 mm ) - 0.5 mm ) - 0.1 mm"
equation "d1497 = ( ( ( keyRowTwo ) - 1.2 mm ) - 2 mm ) + faceOriginV"
equation "d1498 = ( ( ( ( layoutGap + keycapSize / 2 + 2 * keyPitch ) + ( -2.5 mm ) - 0.5 mm ) - 0.1 mm ) + ( 1.2 mm ) ) - ( ( ( layoutGap + keycapSize / 2 + 2 * keyPitch ) + ( -2.5 mm ) - 0.5 mm ) - 0.1 mm )"
equation "d1499 = ( ( ( ( ( keyRowTwo ) - 1.2 mm ) - 2 mm ) + faceOriginV ) + ( 4 mm ) ) - ( ( ( ( keyRowTwo ) - 1.2 mm ) - 2 mm ) + faceOriginV )"
equation "d1500 = rearHeight"
equation "d1502 = ( layoutGap + keycapSize / 2 + 2 * keyPitch ) + ( 2.5 mm ) - 1.2 mm"
equation "d1503 = ( ( ( keyRowTwo ) - 1.2 mm ) * cos(caseTilt) + ( holderBottomDepth + holderLidGap ) * sin(caseTilt) ) - 2.5 mm"
equation "d1504 = ( ( ( layoutGap + keycapSize / 2 + 2 * keyPitch ) + ( 2.5 mm ) - 1.2 mm ) + ( 2.4 mm ) ) - ( ( layoutGap + keycapSize / 2 + 2 * keyPitch ) + ( 2.5 mm ) - 1.2 mm )"
equation "d1505 = ( ( ( ( ( keyRowTwo ) - 1.2 mm ) * cos(caseTilt) + ( holderBottomDepth + holderLidGap ) * sin(caseTilt) ) - 2.5 mm ) + ( 5 mm ) ) - ( ( ( ( keyRowTwo ) - 1.2 mm ) * cos(caseTilt) + ( holderBottomDepth + holderLidGap ) * sin(caseTilt) ) - 2.5 mm )"
equation "d1506 = ( frontHeight + ( ( keyRowTwo ) - 1.2 mm ) * sin(caseTilt) - ( holderBottomDepth + holderLidGap ) * cos(caseTilt) ) - bottomThickness - 2 mm"
equation "d1508 = ( layoutGap + keycapSize / 2 + 2 * keyPitch ) + ( 2.5 mm ) - 0.5 mm"
equation "d1509 = ( ( ( keyRowTwo ) - 1.2 mm ) * cos(caseTilt) + ( holderBottomDepth + holderLidGap ) * sin(caseTilt) ) - 1.5 mm"
equation "d1510 = ( ( ( layoutGap + keycapSize / 2 + 2 * keyPitch ) + ( 2.5 mm ) - 0.5 mm ) + ( 1 mm ) ) - ( ( layoutGap + keycapSize / 2 + 2 * keyPitch ) + ( 2.5 mm ) - 0.5 mm )"
equation "d1511 = ( ( ( ( ( keyRowTwo ) - 1.2 mm ) * cos(caseTilt) + ( holderBottomDepth + holderLidGap ) * sin(caseTilt) ) - 1.5 mm ) + ( 3 mm ) ) - ( ( ( ( keyRowTwo ) - 1.2 mm ) * cos(caseTilt) + ( holderBottomDepth + holderLidGap ) * sin(caseTilt) ) - 1.5 mm )"
equation "d1512 = ( frontHeight + ( ( keyRowTwo ) - 1.2 mm ) * sin(caseTilt) - ( holderBottomDepth + holderLidGap ) * cos(caseTilt) ) - bottomThickness + 0.5 mm"
equation "d1514 = ( ( layoutGap + keycapSize / 2 + 2 * keyPitch ) + ( 2.5 mm ) - 0.5 mm ) - 0.1 mm"
equation "d1515 = ( ( ( keyRowTwo ) - 1.2 mm ) - 2 mm ) + faceOriginV"
equation "d1516 = ( ( ( ( layoutGap + keycapSize / 2 + 2 * keyPitch ) + ( 2.5 mm ) - 0.5 mm ) - 0.1 mm ) + ( 1.2 mm ) ) - ( ( ( layoutGap + keycapSize / 2 + 2 * keyPitch ) + ( 2.5 mm ) - 0.5 mm ) - 0.1 mm )"
equation "d1517 = ( ( ( ( ( keyRowTwo ) - 1.2 mm ) - 2 mm ) + faceOriginV ) + ( 4 mm ) ) - ( ( ( ( keyRowTwo ) - 1.2 mm ) - 2 mm ) + faceOriginV )"
equation "d1518 = rearHeight"
equation "d1520 = layoutGap + ( displayWidth - oledBoardWidth ) / 2 - oledFitClearance"
equation "d1521 = ( controlCenter - oledBoardLength / 2 - oledFitClearance ) + faceOriginV"
equation "d1522 = ( ( layoutGap + ( displayWidth - oledBoardWidth ) / 2 - oledFitClearance ) + ( oledBoardWidth + 2 * oledFitClearance ) ) - ( layoutGap + ( displayWidth - oledBoardWidth ) / 2 - oledFitClearance )"
equation "d1523 = ( ( ( controlCenter - oledBoardLength / 2 - oledFitClearance ) + faceOriginV ) + ( oledBoardLength + 2 * oledFitClearance ) ) - ( ( controlCenter - oledBoardLength / 2 - oledFitClearance ) + faceOriginV )"
equation "d1524 = -( oledBackDepth + oledFitClearance - shellWall - carrierClearance )"
equation "d1526 = ( 115 mm ) - 11 mm"
equation "d1527 = ( ( keyRowOne ) - 11 mm ) + faceOriginV"
equation "d1528 = ( ( ( 115 mm ) - 11 mm ) + ( 22 mm ) ) - ( ( 115 mm ) - 11 mm )"
equation "d1529 = ( ( ( ( keyRowOne ) - 11 mm ) + faceOriginV ) + ( 22 mm ) ) - ( ( ( keyRowOne ) - 11 mm ) + faceOriginV )"
equation "d1530 = -( carrierThickness )"
equation "d1532 = ( 115 mm ) - switchOpening / 2"
equation "d1533 = ( ( keyRowOne ) - switchOpening / 2 ) + faceOriginV"
equation "d1534 = ( ( ( 115 mm ) - switchOpening / 2 ) + ( switchOpening ) ) - ( ( 115 mm ) - switchOpening / 2 )"
equation "d1535 = ( ( ( ( keyRowOne ) - switchOpening / 2 ) + faceOriginV ) + ( switchOpening ) ) - ( ( ( keyRowOne ) - switchOpening / 2 ) + faceOriginV )"
equation "d1536 = -( carrierThickness + 0.1 mm )"
equation "d1538 = ( 115 mm ) - holderFrameX / 2"
equation "d1539 = ( ( keyRowOne ) - holderFrameY / 2 ) + faceOriginV"
equation "d1540 = ( ( ( 115 mm ) - holderFrameX / 2 ) + ( holderFrameX ) ) - ( ( 115 mm ) - holderFrameX / 2 )"
equation "d1541 = ( ( ( ( keyRowOne ) - holderFrameY / 2 ) + faceOriginV ) + ( holderFrameY ) ) - ( ( ( keyRowOne ) - holderFrameY / 2 ) + faceOriginV )"
equation "d1542 = -( holderBottomDepth + holderHookThickness - shellWall - carrierClearance - carrierThickness )"
equation "d1544 = ( 115 mm ) - holderSwitchVoid / 2"
equation "d1545 = ( ( keyRowOne ) - holderSwitchVoid / 2 ) + faceOriginV"
equation "d1546 = ( ( ( 115 mm ) - holderSwitchVoid / 2 ) + ( holderSwitchVoid ) ) - ( ( 115 mm ) - holderSwitchVoid / 2 )"
equation "d1547 = ( ( ( ( keyRowOne ) - holderSwitchVoid / 2 ) + faceOriginV ) + ( holderSwitchVoid ) ) - ( ( ( keyRowOne ) - holderSwitchVoid / 2 ) + faceOriginV )"
equation "d1548 = -( holderTopDepth - shellWall - carrierClearance - carrierThickness )"
equation "d1550 = ( 115 mm ) - holderWidth / 2 - holderFit"
equation "d1551 = ( ( keyRowOne ) - holderLength / 2 - holderFit ) + faceOriginV"
equation "d1552 = ( ( ( 115 mm ) - holderWidth / 2 - holderFit ) + ( holderWidth + 2 * holderFit ) ) - ( ( 115 mm ) - holderWidth / 2 - holderFit )"
equation "d1553 = ( ( ( ( keyRowOne ) - holderLength / 2 - holderFit ) + faceOriginV ) + ( holderLength + 2 * holderFit ) ) - ( ( ( keyRowOne ) - holderLength / 2 - holderFit ) + faceOriginV )"
equation "d1554 = -( holderHeight + holderHookThickness + 0.2 mm )"
equation "d1556 = ( 115 mm ) - holderFrameX / 2 - 0.1 mm"
equation "d1557 = ( ( ( keyRowOne ) + holderSpringY ) - holderSpringWidth / 2 - 0.6 mm ) + faceOriginV"
equation "d1558 = ( ( ( 115 mm ) - holderFrameX / 2 - 0.1 mm ) + ( holderFrameX / 2 - holderWidth / 2 - holderFit + 0.1 mm ) ) - ( ( 115 mm ) - holderFrameX / 2 - 0.1 mm )"
equation "d1559 = ( ( ( ( ( keyRowOne ) + holderSpringY ) - holderSpringWidth / 2 - 0.6 mm ) + faceOriginV ) + ( 0.6 mm ) ) - ( ( ( ( keyRowOne ) + holderSpringY ) - holderSpringWidth / 2 - 0.6 mm ) + faceOriginV )"
equation "d1560 = -( holderBottomDepth + holderHookThickness - shellWall - carrierClearance - carrierThickness - 1 mm + 0.2 mm )"
equation "d1562 = ( 115 mm ) - holderFrameX / 2 - 0.1 mm"
equation "d1563 = ( ( ( keyRowOne ) + holderSpringY ) + holderSpringWidth / 2 ) + faceOriginV"
equation "d1564 = ( ( ( 115 mm ) - holderFrameX / 2 - 0.1 mm ) + ( holderFrameX / 2 - holderWidth / 2 - holderFit + 0.1 mm ) ) - ( ( 115 mm ) - holderFrameX / 2 - 0.1 mm )"
equation "d1565 = ( ( ( ( ( keyRowOne ) + holderSpringY ) + holderSpringWidth / 2 ) + faceOriginV ) + ( 0.6 mm ) ) - ( ( ( ( keyRowOne ) + holderSpringY ) + holderSpringWidth / 2 ) + faceOriginV )"
equation "d1566 = -( holderBottomDepth + holderHookThickness - shellWall - carrierClearance - carrierThickness - 1 mm + 0.2 mm )"
equation "d1568 = ( 115 mm ) - holderFrameX / 2 + 0.8 mm"
equation "d1569 = ( ( ( keyRowOne ) + holderSpringY ) - holderSpringWidth / 2 ) + faceOriginV"
equation "d1570 = ( ( ( 115 mm ) - holderFrameX / 2 + 0.8 mm ) + ( holderFrameX / 2 - 0.8 mm - holderWidth / 2 - holderFit ) ) - ( ( 115 mm ) - holderFrameX / 2 + 0.8 mm )"
equation "d1571 = ( ( ( ( ( keyRowOne ) + holderSpringY ) - holderSpringWidth / 2 ) + faceOriginV ) + ( holderSpringWidth ) ) - ( ( ( ( keyRowOne ) + holderSpringY ) - holderSpringWidth / 2 ) + faceOriginV )"
equation "d1572 = -( holderHeight + holderHookThickness + 0.2 mm )"
equation "d1574 = ( 115 mm ) - holderFrameX / 2"
equation "d1575 = ( ( ( keyRowOne ) + holderSpringY ) - holderSpringWidth / 2 ) + faceOriginV"